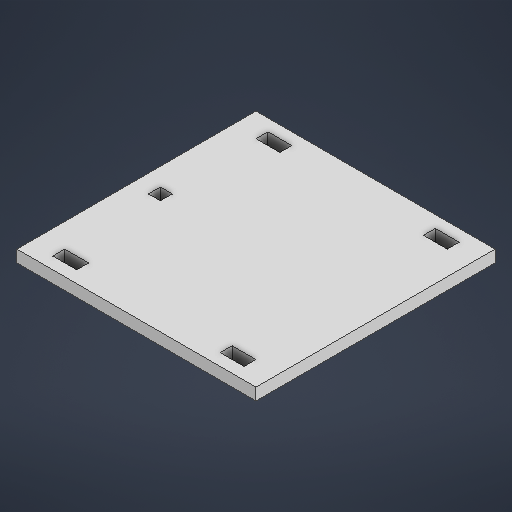
# Autodesk Inventor part: Medio
Saved by Autodesk Inventor 2025.2 (Build 292293000, 293)
## iProperties
Created: 2025-06-04
Part Number: Medio
Material: Genérico
Document SubType Name: Modeling
Designer: Niko
Density: 1 g/cm^3
Appearance: Valor por defecto
Author: Niko
Autodesk Inventor part; units mm, degrees
ref_plane "YZ Plane" through (0, 0, 0) normal (1, 0, 0) x (0, 1, 0)
ref_plane "XZ Plane" through (0, 0, 0) normal (0, 1, 0) x (-1, 0, 0)
ref_plane "XY Plane" through (0, 0, 0) normal (0, 0, 1) x (1, 0, 0)
sketch "Boceto1" plane through (0, 0, 0) normal (0, 1, 0) x (-1, 0, 0)
  line L0 (50, 50) -> (-50, 50)
  line L1 (-50, 50) -> (-50, -50)
  line L2 (-50, -50) -> (50, -50)
  line L3 (50, -50) -> (50, 50)
  line L4 (50, 30) -> (50, 50)
  line L5 (50, 50) -> (50, 45)
  line L6 (40, 45) -> (30, 45)
  line L7 (30, 45) -> (30, 40)
  line L8 (30, 40) -> (40, 40)
  line L9 (40, 40) -> (40, 45)
  line L10 (-40, 45) -> (-30, 45)
  line L11 (-30, 45) -> (-30, 40)
  line L12 (-30, 40) -> (-40, 40)
  line L13 (-40, 40) -> (-40, 45)
  line L14 (40, -45) -> (30, -45)
  line L15 (30, -45) -> (30, -40)
  line L16 (30, -40) -> (40, -40)
  line L17 (40, -40) -> (40, -45)
  line L18 (-30, -45) -> (-30, -40)
  line L19 (-30, -40) -> (-40, -40)
  line L20 (-40, -40) -> (-40, -45)
  line L21 (-40, -45) -> (-30, -45)
  line L22 (40, -2.5) -> (42.5, -2.5)
  line L23 (42.5, -2.5) -> (37.5, -2.5)
  line L24 (37.5, -2.5) -> (37.5, 2.5)
  line L25 (37.5, 2.5) -> (42.5, 2.5)
  line L26 (42.5, 2.5) -> (42.5, -2.5)
  constraints: 54 end point, 6 parallel, 4 horizontal, 3 perpendicular, 1 point on line
extrude "Extrusión3" add sketch "Boceto1" along normal blind 5
